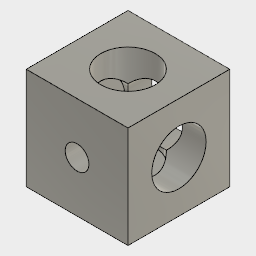
RailCoreII-ZL v1 (Autodesk Fusion 360 archive; units mm, degrees)
design "CornerBlock v1"
Autodesk Fusion 360 part; units mm, degrees
note: some values were not read from the file. Set by a fixed rule: which sketch regions a step uses.
box "BoxPrimitive1" add length 15 width 15 height 15 placed x (0, 1, 0) y (-1, 0, 0) z (0, 0, 1) at (15, 0, 0)
hole "Hole1" at (7.5, 7.5, 15) direction (0, 0, -1) diameter 3.5 depth 15 tip angle 118 counterbore diameter 8 counterbore depth 12
hole "Hole2" at (15, 7.5, 7.5) direction (-1, 0, 0) diameter 3.5 depth 15 tip angle 118 counterbore diameter 8 counterbore depth 12
hole "Hole3" at (7.5, 15, 7.5) direction (0, -1, 0) diameter 3.5 depth 15 tip angle 118 counterbore diameter 8 counterbore depth 12

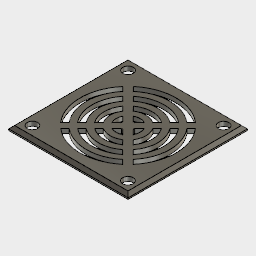
design "Fan_Cover"
Autodesk Fusion 360 part; units mm, degrees
sketch "Sketch1" plane through (0, 0, 0) normal (0, 0, 1) x (1, 0, 0)
  circle A0 centre (1.9885, 1.9886) radius 1.75
  circle A1 centre (2.0234, 33.9886) radius 1.75
  circle A2 centre (34.0234, 33.9537) radius 1.75
  circle A3 centre (33.9885, 1.9537) radius 1.75
  line L0 (-2.0115, 37.9886) -> (37.9885, 37.9886)
  line L1 (37.9885, 37.9886) -> (37.9885, -2.0114)
  line L2 (37.9885, -2.0114) -> (-2.0115, -2.0114)
  line L3 (-2.0115, -2.0114) -> (-2.0115, 37.9886)
  circle A4 centre (18, 18) radius 2
  circle A5 centre (18, 18) radius 4
  circle A6 centre (18, 18) radius 6
  circle A7 centre (18, 18) radius 8
  circle A8 centre (18, 18) radius 10
  circle A9 centre (18, 18) radius 14
  circle A10 centre (18, 18) radius 12
  line L4 (1.9885, 1.9886) -> (34.0234, 33.9537) construction
  line L5 (2.0234, 33.9886) -> (33.9885, 1.9537) construction
  circle A11 centre (18, 18) radius 16
  line L6 (7.6057, 30.1638) -> (30.1411, 7.5792)
  line L7 (5.8378, 28.3962) -> (28.3696, 5.8152)
  line L8 (28.4273, 30.1356) -> (5.8417, 7.5992)
  line L9 (7.6103, 5.8322) -> (30.1904, 28.3632)
  dimension "d1" = 3.5
  dimension "d2" = 3.5
  dimension "d3" = 3.5
  dimension "d4" = 3.5
  dimension "d5" = 32
  dimension "d6" = 32
  dimension "d7" = 32
  dimension "d8" = 32
  dimension "d14" = 4
  dimension "d15" = 4
  dimension "d16" = 4
  dimension "d17" = 4
  dimension "d18" = 4
  dimension "d30" = 8
  dimension "d31" = 12
  dimension "d32" = 16
  dimension "d33" = 20
  dimension "d34" = 28
  dimension "d35" = 24
  dimension "d41" = 32
  dimension "d42" = 1.25
  dimension "d43" = 1.25
  dimension "d44" = 1.25
  dimension "d45" = 1.25
  measures "d1" diameter of A0
  measures "d2" diameter of A1
  measures "d3" diameter of A2
  measures "d4" diameter of A3
  measures "d5" distance of A0.centre A3.centre
  measures "d6" distance of A0.centre A1.centre
  measures "d7" distance of A1.centre A2.centre
  measures "d8" distance of A2.centre A3.centre
  measures "d14" distance of A0.centre L3
  measures "d15" distance of A3.centre L1
  measures "d16" distance of A1.centre L0
  measures "d17" distance of A0.centre L2
  measures "d18" diameter of A4
  measures "d30" diameter of A5
  measures "d31" diameter of A6
  measures "d32" diameter of A7
  measures "d33" diameter of A8
  measures "d34" diameter of A9
  measures "d35" diameter of A10
  measures "d41" diameter of A11
  measures "d42" distance of L5 L7
  measures "d43" distance of L5 L6
  measures "d44" distance of L4 L8
  measures "d45" distance of L4 L9
extrude "Extrude1" add sketch "Sketch1" along normal blind 1.5 contours L0 L1 L2 L3 | A4 L6 L9 | A4 L6 L8 L9 | A4 A5 L8 L9 | A4 A5 L6 L7 | A4 L6 L7 L9 | A4 L6 L8 | L6 L7 L8 L9 | A5 A6 L6 L9 | A5 A6 L8 L9 | A4 L7 L9 | A5 A6 L6 L7 | A4 L6 L7 L8 | A4 A5 L6 L7 | A5 A6 L6 L8 | A4 L7 L8 L9 | A6 A7 L8 L9 | A4 A5 L8 L9 | A5 A6 L7 L9 | A6 A7 L6 L7 | A4 L7 L8 | A5 A6 L6 L7 | A7 A8 L6 L9 | A7 A8 L8 L9 | A5 A6 L8 L9 | A7 A8 L6 L7 | A5 A6 L7 L8 | A6 A7 L6 L7 | A7 A8 L6 L8 | A8 A10 L8 L9 | A6 A7 L8 L9 | A7 A8 L7 L9 | A8 A10 L6 L7 | A7 A8 L6 L7 | A9 A10 L6 L9 | A9 A10 L8 L9 | A7 A8 L8 L9 | A9 A10 L6 L7 | A7 A8 L7 L8 | A8 A10 L6 L7 | A9 A10 L6 L8 | A9 A11 L8 L9 | A8 A10 L8 L9 | A9 A10 L7 L9 | A9 A11 L6 L7 | A9 A10 L6 L7 | A9 A10 L8 L9 | A9 A10 L7 L8 | A9 A11 L6 L7 | A9 A11 L8 L9
chamfer "Chamfer1" distance 1 angle 45 4 edges at (17.9885, -2.0114, 1.5) (37.9885, 17.9886, 1.5) (-2.0115, 17.9886, 1.5) (17.9885, 37.9886, 1.5)

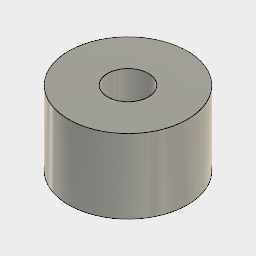
design "Idler_Spacer"
Autodesk Fusion 360 part; units mm, degrees
sketch "Sketch1" plane through (0, 0, 0) normal (0, 0, 1) x (1, 0, 0)
  circle A0 centre (0, 0) radius 2.75
  circle A1 centre (0, 0) radius 8
  dimension "d1" = 5.5
  measures "d1" diameter of A0
extrude "Extrude1" add sketch "Sketch1" along normal blind 10

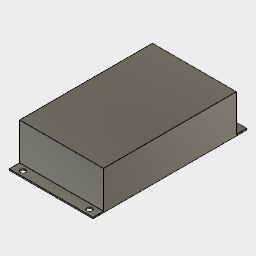
design "PSU v2"
Autodesk Fusion 360 part; units mm, degrees
sketch "Sketch1" plane through (0, 0, 0) normal (0, 0, 1) x (1, 0, 0)
  line L0 (0, 0) -> (120, 0)
  line L1 (120, 0) -> (120, -220)
  line L2 (120, -220) -> (0, -220)
  line L3 (0, -220) -> (0, 0)
  line L4 (0, -15) -> (120, -15)
  line L5 (0, -205) -> (120, -205)
  circle A0 centre (12.5, -212.5) radius 3.75
  circle A1 centre (107.5, -212.5) radius 3.75
  circle A2 centre (12.5, -7.5) radius 3.75
  circle A3 centre (107.5, -7.5) radius 3.75
  dimension "d1" = 220
  dimension "d2" = 120
  dimension "d3" = 15
  dimension "d4" = 15
  dimension "d5" = 7.5
  dimension "d6" = 7.5
  dimension "d7" = 12.5
  dimension "d8" = 7.5
  dimension "d9" = 7.5
  dimension "d10" = 12.5
  dimension "d11" = 7.5
  dimension "d12" = 7.5
  dimension "d13" = 12.5
  dimension "d14" = 7.5
  dimension "d15" = 12.5
  dimension "d16" = 7.5
  measures "d1" distance of L0.start L2.end
  measures "d2" distance of L0.start L0.end
  measures "d3" distance of L0 L4
  measures "d4" distance of L2 L5
  measures "d5" diameter of A0
  measures "d6" diameter of A1
  measures "d7" distance of L3 A0.centre
  measures "d8" distance of L2 A0.centre
  measures "d9" distance of L2 A1.centre
  measures "d10" distance of L1 A1.centre
  measures "d11" diameter of A2
  measures "d12" diameter of A3
  measures "d13" distance of L3 A2.centre
  measures "d14" distance of L0 A2.centre
  measures "d15" distance of L1 A3.centre
  measures "d16" distance of L0 A3.centre
extrude "Extrude1" add sketch "Sketch1" along normal blind 2 contours L0 L1 L3 L4 | L1 L2 L3 L5 makes body 1 at (2.9167, -7.5, 0) makes body 2 at (117.0833, -212.5, 0)
extrude "Extrude2" add sketch "Sketch1" along normal blind 55 contours L1 L3 L4 L5 bodies 1 2

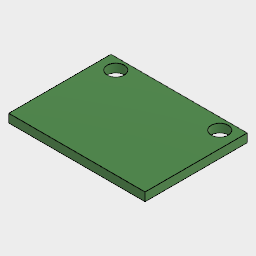
design "Dummy_IR_Probe"
Autodesk Fusion 360 part; units mm, degrees
sketch "Sketch1" plane through (0, 0, 0) normal (0, 0, 1) x (1, 0, 0) in component "DummyIRProbe v1"
  line L0 (-12, 9) -> (12, 9)
  line L1 (12, 9) -> (12, -9)
  line L2 (12, -9) -> (-12, -9)
  line L3 (-12, -9) -> (-12, 9)
  line L4 (-12, 9) -> (12, -9) construction
  line L5 (12, 9) -> (-12, -9) construction
  line L6 (0, 7) -> (9.15, 7) construction
  line L7 (0, 7) -> (-9.15, 7) construction
  circle A0 centre (-9.15, 7) radius 1.5
  circle A1 centre (9.15, 7) radius 1.5
  dimension "d1_1_1_1" = 24
  dimension "d2_1_1_1" = 9.15
  dimension "d3_1_1_1" = 9.15
  dimension "d4_1_1_1" = 3
  dimension "d5_1_1" = 3
  measures "d1_1_1_1" distance of L1.end L2.end
  measures "d2_1_1_1" distance of L6.start L6.end
  measures "d3_1_1_1" distance of L6.start L7.end
  measures "d4_1_1_1" diameter of A0
  measures "d5_1_1" diameter of A1
extrude "Extrude1" add sketch "Sketch1" along normal blind 1.5 in component "DummyIRProbe v1"
component "DummyIRProbe v1" placed x (1, 0, 0) y (0, 1, 0) z (0, 0, 1) at (-8.9387, -37.5727, -33.3823)
